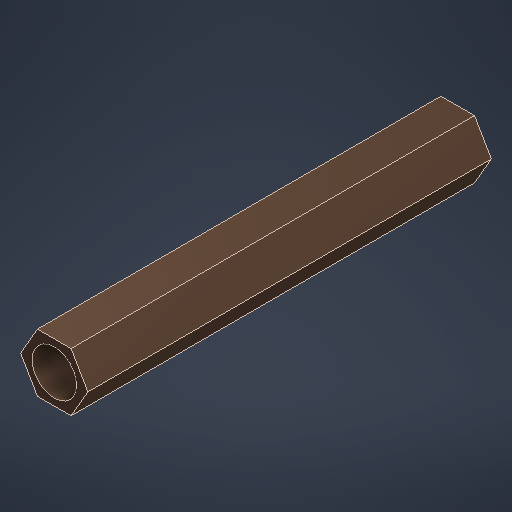
# Autodesk Inventor part: SOPORTES_DOBLE_ROSCADOS
Saved by Autodesk Inventor 2026.2 (Build 302298010, 298A)
## iProperties
Created: 2026-10-27
Part Number: SOPORTES_DOBLE_ROSCADOS
Material: Bronce, fundido
Document SubType Name: Modeling
Designer: efrey
Density: 8.87 g/cm^3
Appearance: Bronce - Satinado
Author: efrey
Autodesk Inventor part; units mm, degrees
ref_plane "YZ Plane" through (0, 0, 0) normal (1, 0, 0) x (0, 1, 0)
ref_plane "XZ Plane" through (0, 0, 0) normal (0, 1, 0) x (-1, 0, 0)
ref_plane "XY Plane" through (0, 0, 0) normal (0, 0, 1) x (1, 0, 0)
sketch "Boceto1" plane through (0, 0, 0) normal (0, 0, 1) x (1, 0, 0)
  line L0 (2.5, 0) -> (1.25, -2.1651)
  line L1 (1.25, -2.1651) -> (-1.25, -2.1651)
  line L2 (-1.25, -2.1651) -> (-2.5, 0)
  line L3 (-2.5, 0) -> (-1.25, 2.1651)
  line L4 (-1.25, 2.1651) -> (1.25, 2.1651)
  line L5 (1.25, 2.1651) -> (2.5, 0)
  point P0 (0, 0)
  point P1 (0, 0)
  dimension "d0" = 2.5
  constraints: 12 end point, 1 coincident, 1 horizontal, 13 other
  measures "d0" distance of point (0, 0) L2.end
extrude "Extrusión1" add sketch "Boceto1" along normal mid plane 30
sketch "Boceto2" plane through (0, 0, 15) normal (0, 0, 1) x (1, 0, 0)
  circle A0 centre (0, 0) radius 1.65
  dimension "d4" = 3.3
  constraints: 1 centre point, 1 coincident
  measures "d4" diameter of A0
hole "Agujero1" at (0, 0, 15) direction (0, 0, -1) diameter 3.3 depth 5 tip angle 118
sketch "Boceto3" plane through (0, 0, -15) normal (0, 0, -1) x (-1, 0, 0)
  circle A0 centre (0, 0) radius 1.65 projected
  circle A1 centre (0, 0) radius 1.65
  dimension "d12" = 3.3
  constraints: 1 centre point, 1 coincident
  measures "d12" diameter of A1
hole "Agujero2" at (0, 0, -15) direction (0, 0, 1) diameter 3.3 depth 5 tip angle 118
